210103_P01_WALL-PANEL-ASSY-SIDE-UPPER-LH_CAD (Autodesk Fusion 360 design; units mm, degrees)
part number: 2026-11-01-01-54-37-587
description: WALL - PANEL FRAME - SIDE UPPER - LH | Vách trái - khung trên | P01
part number: 211103
description: WALL - SKIN - SIDE UPPER - LH | Vách trái - tấm ốp alu trên | P01
part number: 211303
description: WALL - CAVITY FILL - SIDE UPPER - LH | Vách trái - bông PET trên | P01
part number: 211503
description: HARDWARE - STOP WASHER - Ø10.5 X Ø20 X 1.5 - AL | Long đen chặn nhôm | P01
part number: 831002
description: HARDWARE - RIVET NUT - M6 - SHEREX CAH3-610-4.2 | Tán rút M6 | P01
part number: 838003
Autodesk Fusion 360 part; units mm, degrees
(part 1 of 2)
ref_plane "WorkPlane1" through (0, 0, 1257.26) normal (0, 0, 1) x (1, 0, 0) in component "211103 WALL - PANEL FRAME - SIDE UPPER - LH"
sketch "SKETCH - RAIL - BOTTOM TUBE" plane through (0, 0, 1257.26) normal (0, 0, 1) x (1, 0, 0) in component "211103 WALL - PANEL FRAME - SIDE UPPER - LH"
  line L0 (-1244, -642.74) -> (-1204, -642.74)
  line L1 (-1204, -642.74) -> (-1204, 847)
  line L2 (-1204, 847) -> (-1244, 847)
  line L3 (-1244, 847) -> (-1244, -642.74)
  dimension "d662" = 40
  dimension "d663" = 1489.74
  dimension "d664" = 1244
  dimension "d665" = 642.74
  constraint horizontal L0
  constraint vertical L1
  constraint horizontal L2
  constraint vertical L3
  measures "d662" horizontal distance of L0.start L0.end
  measures "d663" vertical distance of L0.start L2.end
  measures "d664" horizontal distance of origin L0.start
  measures "d665" vertical distance of origin L0.start
extrude "EXTRUDE - RAIL - BOTTOM TUBE" add sketch "SKETCH - RAIL - BOTTOM TUBE" along normal blind 20 makes body 1 in component "211103 WALL - PANEL FRAME - SIDE UPPER - LH"
ref_plane "WorkPlane2" through (0, 0, 1258.46) normal (0, 0, 1) x (1, 0, 0) in component "211103 WALL - PANEL FRAME - SIDE UPPER - LH"
sketch "SKETCH - RAIL - BOTTOM BORE" plane through (0, 0, 1258.46) normal (0, 0, 1) x (1, 0, 0) in component "211103 WALL - PANEL FRAME - SIDE UPPER - LH"
  line L0 (-1242.8, -642.74) -> (-1205.2, -642.74)
  line L1 (-1205.2, -642.74) -> (-1205.2, 847)
  line L2 (-1205.2, 847) -> (-1242.8, 847)
  line L3 (-1242.8, 847) -> (-1242.8, -642.74)
  dimension "d670" = 37.6
  dimension "d671" = 1489.74
  dimension "d672" = 1242.8
  dimension "d673" = 642.74
  constraint horizontal L0
  constraint vertical L1
  constraint horizontal L2
  constraint vertical L3
  measures "d670" horizontal distance of L0.start L0.end
  measures "d671" vertical distance of L0.start L2.end
  measures "d672" horizontal distance of origin L0.start
  measures "d673" vertical distance of origin L0.start
extrude "CUT - RAIL - BOTTOM BORE" cut sketch "SKETCH - RAIL - BOTTOM BORE" along normal blind 17.6 bodies 1 in component "211103 WALL - PANEL FRAME - SIDE UPPER - LH"
ref_plane "WorkPlane3" through (0, 0, 2360) normal (0, 0, 1) x (1, 0, 0) in component "211103 WALL - PANEL FRAME - SIDE UPPER - LH"
sketch "SKETCH - RAIL - TOP TUBE" plane through (0, 0, 2360) normal (0, 0, 1) x (1, 0, 0) in component "211103 WALL - PANEL FRAME - SIDE UPPER - LH"
  line L0 (-1244, -642.74) -> (-1204, -642.74)
  line L1 (-1204, -642.74) -> (-1204, 847)
  line L2 (-1204, 847) -> (-1244, 847)
  line L3 (-1244, 847) -> (-1244, -642.74)
  dimension "d678" = 40
  dimension "d679" = 1489.74
  dimension "d680" = 1244
  dimension "d681" = 642.74
  constraint horizontal L0
  constraint vertical L1
  constraint horizontal L2
  constraint vertical L3
  measures "d678" horizontal distance of L0.start L0.end
  measures "d679" vertical distance of L0.start L2.end
  measures "d680" horizontal distance of origin L0.start
  measures "d681" vertical distance of origin L0.start
extrude "EXTRUDE - RAIL - TOP TUBE" add sketch "SKETCH - RAIL - TOP TUBE" along normal blind 40 separate body makes body 2 in component "211103 WALL - PANEL FRAME - SIDE UPPER - LH"
ref_plane "WorkPlane4" through (0, 0, 2361.2) normal (0, 0, 1) x (1, 0, 0) in component "211103 WALL - PANEL FRAME - SIDE UPPER - LH"
sketch "SKETCH - RAIL - TOP BORE" plane through (0, 0, 2361.2) normal (0, 0, 1) x (1, 0, 0) in component "211103 WALL - PANEL FRAME - SIDE UPPER - LH"
  line L0 (-1242.8, -642.74) -> (-1205.2, -642.74)
  line L1 (-1205.2, -642.74) -> (-1205.2, 847)
  line L2 (-1205.2, 847) -> (-1242.8, 847)
  line L3 (-1242.8, 847) -> (-1242.8, -642.74)
  dimension "d686" = 37.6
  dimension "d687" = 1489.74
  dimension "d688" = 1242.8
  dimension "d689" = 642.74
  constraint horizontal L0
  constraint vertical L1
  constraint horizontal L2
  constraint vertical L3
  measures "d686" horizontal distance of L0.start L0.end
  measures "d687" vertical distance of L0.start L2.end
  measures "d688" horizontal distance of origin L0.start
  measures "d689" vertical distance of origin L0.start
extrude "CUT - RAIL - TOP BORE" cut sketch "SKETCH - RAIL - TOP BORE" along normal blind 37.6 bodies 2 in component "211103 WALL - PANEL FRAME - SIDE UPPER - LH"
ref_plane "WorkPlane5" through (0, 0, 1277.26) normal (0, 0, 1) x (1, 0, 0) in component "211103 WALL - PANEL FRAME - SIDE UPPER - LH"
sketch "SKETCH - STILE - FRONT TUBE" plane through (0, 0, 1277.26) normal (0, 0, 1) x (1, 0, 0) in component "211103 WALL - PANEL FRAME - SIDE UPPER - LH"
  line L0 (-1244, -642.74) -> (-1204, -642.74)
  line L1 (-1204, -642.74) -> (-1204, -622.74)
  line L2 (-1204, -622.74) -> (-1244, -622.74)
  line L3 (-1244, -622.74) -> (-1244, -642.74)
  dimension "d694" = 40
  dimension "d695" = 20
  dimension "d696" = 1244
  dimension "d697" = 642.74
  constraint horizontal L0
  constraint vertical L1
  constraint horizontal L2
  constraint vertical L3
  measures "d694" horizontal distance of L0.start L0.end
  measures "d695" vertical distance of L0.start L2.end
  measures "d696" horizontal distance of origin L0.start
  measures "d697" vertical distance of origin L0.start
extrude "EXTRUDE - STILE - FRONT TUBE" add sketch "SKETCH - STILE - FRONT TUBE" along normal blind 1082.74 separate body makes body 3 in component "211103 WALL - PANEL FRAME - SIDE UPPER - LH"
ref_plane "WorkPlane6" through (0, 0, 1277.26) normal (0, 0, 1) x (1, 0, 0) in component "211103 WALL - PANEL FRAME - SIDE UPPER - LH"
sketch "SKETCH - STILE - FRONT BORE" plane through (0, 0, 1277.26) normal (0, 0, 1) x (1, 0, 0) in component "211103 WALL - PANEL FRAME - SIDE UPPER - LH"
  line L0 (-1242.8, -641.54) -> (-1205.2, -641.54)
  line L1 (-1205.2, -641.54) -> (-1205.2, -623.94)
  line L2 (-1205.2, -623.94) -> (-1242.8, -623.94)
  line L3 (-1242.8, -623.94) -> (-1242.8, -641.54)
  dimension "d702" = 37.6
  dimension "d703" = 17.6
  dimension "d704" = 1242.8
  dimension "d705" = 641.54
  constraint horizontal L0
  constraint vertical L1
  constraint horizontal L2
  constraint vertical L3
  measures "d702" horizontal distance of L0.start L0.end
  measures "d703" vertical distance of L0.start L2.end
  measures "d704" horizontal distance of origin L0.start
  measures "d705" vertical distance of origin L0.start
extrude "CUT - STILE - FRONT BORE" cut sketch "SKETCH - STILE - FRONT BORE" along normal blind 1082.74 bodies 3 in component "211103 WALL - PANEL FRAME - SIDE UPPER - LH"
ref_plane "WorkPlane7" through (0, 0, 1277.26) normal (0, 0, 1) x (1, 0, 0) in component "211103 WALL - PANEL FRAME - SIDE UPPER - LH"
sketch "SKETCH - STILE - BACK TUBE" plane through (0, 0, 1277.26) normal (0, 0, 1) x (1, 0, 0) in component "211103 WALL - PANEL FRAME - SIDE UPPER - LH"
  line L0 (-1244, 807) -> (-1204, 807)
  line L1 (-1204, 807) -> (-1204, 847)
  line L2 (-1204, 847) -> (-1244, 847)
  line L3 (-1244, 847) -> (-1244, 807)
  dimension "d710" = 40
  dimension "d711" = 40
  dimension "d712" = 1244
  dimension "d713" = 807
  constraint horizontal L0
  constraint vertical L1
  constraint horizontal L2
  constraint vertical L3
  measures "d710" horizontal distance of L0.start L0.end
  measures "d711" vertical distance of L0.start L2.end
  measures "d712" horizontal distance of origin L0.start
  measures "d713" vertical distance of origin L0.start
extrude "EXTRUDE - STILE - BACK TUBE" add sketch "SKETCH - STILE - BACK TUBE" along normal blind 1082.74 separate body makes body 4 in component "211103 WALL - PANEL FRAME - SIDE UPPER - LH"
ref_plane "WorkPlane8" through (0, 0, 1277.26) normal (0, 0, 1) x (1, 0, 0) in component "211103 WALL - PANEL FRAME - SIDE UPPER - LH"
sketch "SKETCH - STILE - BACK BORE" plane through (0, 0, 1277.26) normal (0, 0, 1) x (1, 0, 0) in component "211103 WALL - PANEL FRAME - SIDE UPPER - LH"
  line L0 (-1242.8, 808.2) -> (-1205.2, 808.2)
  line L1 (-1205.2, 808.2) -> (-1205.2, 845.8)
  line L2 (-1205.2, 845.8) -> (-1242.8, 845.8)
  line L3 (-1242.8, 845.8) -> (-1242.8, 808.2)
  dimension "d718" = 37.6
  dimension "d719" = 37.6
  dimension "d720" = 1242.8
  dimension "d721" = 808.2
  constraint horizontal L0
  constraint vertical L1
  constraint horizontal L2
  constraint vertical L3
  measures "d718" horizontal distance of L0.start L0.end
  measures "d719" vertical distance of L0.start L2.end
  measures "d720" horizontal distance of origin L0.start
  measures "d721" vertical distance of origin L0.start
extrude "CUT - STILE - BACK BORE" cut sketch "SKETCH - STILE - BACK BORE" along normal blind 1082.74 bodies 4 in component "211103 WALL - PANEL FRAME - SIDE UPPER - LH"
ref_plane "WorkPlane9" through (0, 0, 1277.26) normal (0, 0, 1) x (1, 0, 0) in component "211103 WALL - PANEL FRAME - SIDE UPPER - LH"
sketch "SKETCH - STILE - MID 1 TUBE" plane through (0, 0, 1277.26) normal (0, 0, 1) x (1, 0, 0) in component "211103 WALL - PANEL FRAME - SIDE UPPER - LH"
  line L0 (-1244, -277.805) -> (-1204, -277.805)
  line L1 (-1204, -277.805) -> (-1204, -257.805)
  line L2 (-1204, -257.805) -> (-1244, -257.805)
  line L3 (-1244, -257.805) -> (-1244, -277.805)
  dimension "d726" = 40
  dimension "d727" = 20
  dimension "d728" = 1244
  dimension "d729" = 277.805
  constraint horizontal L0
  constraint vertical L1
  constraint horizontal L2
  constraint vertical L3
  measures "d726" horizontal distance of L0.start L0.end
  measures "d727" vertical distance of L0.start L2.end
  measures "d728" horizontal distance of origin L0.start
  measures "d729" vertical distance of origin L0.start
extrude "EXTRUDE - STILE - MID 1 TUBE" add sketch "SKETCH - STILE - MID 1 TUBE" along normal blind 1082.74 separate body makes body 5 in component "211103 WALL - PANEL FRAME - SIDE UPPER - LH"
ref_plane "WorkPlane10" through (0, 0, 1277.26) normal (0, 0, 1) x (1, 0, 0) in component "211103 WALL - PANEL FRAME - SIDE UPPER - LH"
sketch "SKETCH - STILE - MID 1 BORE" plane through (0, 0, 1277.26) normal (0, 0, 1) x (1, 0, 0) in component "211103 WALL - PANEL FRAME - SIDE UPPER - LH"
  line L0 (-1243, -276.805) -> (-1205, -276.805)
  line L1 (-1205, -276.805) -> (-1205, -258.805)
  line L2 (-1205, -258.805) -> (-1243, -258.805)
  line L3 (-1243, -258.805) -> (-1243, -276.805)
  dimension "d734" = 38
  dimension "d735" = 18
  dimension "d736" = 1243
  dimension "d737" = 276.805
  constraint horizontal L0
  constraint vertical L1
  constraint horizontal L2
  constraint vertical L3
  measures "d734" horizontal distance of L0.start L0.end
  measures "d735" vertical distance of L0.start L2.end
  measures "d736" horizontal distance of origin L0.start
  measures "d737" vertical distance of origin L0.start
extrude "CUT - STILE - MID 1 BORE" cut sketch "SKETCH - STILE - MID 1 BORE" along normal blind 1082.74 bodies 5 in component "211103 WALL - PANEL FRAME - SIDE UPPER - LH"
pattern_linear "PATTERN - STILES - MID" count 3 spacing 364.935 along (0, 1, 0) of bodies 5 makes body 6 at (-1217.3333, 107.13, 1999.0867) makes body 7 at (-1217.3333, 472.065, 1999.0867) in component "211103 WALL - PANEL FRAME - SIDE UPPER - LH"
ref_plane "WorkPlane1" through (0, 0, 1257.26) normal (0, 0, 1) x (1, 0, 0) in component "211303 WALL - SKIN - SIDE UPPER - LH"
sketch "SKETCH - SKIN PLATE" plane through (0, 0, 1257.26) normal (0, 0, 1) x (1, 0, 0) in component "211303 WALL - SKIN - SIDE UPPER - LH"
  line L0 (-1250, -642.74) -> (-1247, -642.74)
  line L1 (-1247, -642.74) -> (-1247, 850)
  line L2 (-1247, 850) -> (-1250, 850)
  line L3 (-1250, 850) -> (-1250, -642.74)
  dimension "d746" = 3
  dimension "d747" = 1492.74
  dimension "d748" = 1250
  dimension "d749" = 642.74
  constraint horizontal L0
  constraint vertical L1
  constraint horizontal L2
  constraint vertical L3
  measures "d746" horizontal distance of L0.start L0.end
  measures "d747" vertical distance of L0.start L2.end
  measures "d748" horizontal distance of origin L0.start
  measures "d749" vertical distance of origin L0.start
extrude "EXTRUDE - SKIN PLATE" add sketch "SKETCH - SKIN PLATE" along normal blind 1142.74 separate body makes body 8 in component "211303 WALL - SKIN - SIDE UPPER - LH"
ref_plane "WorkPlane2" through (0, 0, 1257.26) normal (0, 0, 1) x (1, 0, 0) in component "211303 WALL - SKIN - SIDE UPPER - LH"
sketch "SKETCH - SKIN BACK RETURN" plane through (0, 0, 1257.26) normal (0, 0, 1) x (1, 0, 0) in component "211303 WALL - SKIN - SIDE UPPER - LH"
  line L0 (-1247, 847) -> (-1204, 847)
  line L1 (-1204, 847) -> (-1204, 850)
  line L2 (-1204, 850) -> (-1247, 850)
  line L3 (-1247, 850) -> (-1247, 847)
  dimension "d754" = 43
  dimension "d755" = 3
  dimension "d756" = 1247
  dimension "d757" = 847
  constraint horizontal L0
  constraint vertical L1
  constraint horizontal L2
  constraint vertical L3
  measures "d754" horizontal distance of L0.start L0.end
  measures "d755" vertical distance of L0.start L2.end
  measures "d756" horizontal distance of origin L0.start
  measures "d757" vertical distance of origin L0.start
extrude "JOIN - SKIN BACK RETURN" add sketch "SKETCH - SKIN BACK RETURN" along normal blind 1142.74 bodies 8 in component "211303 WALL - SKIN - SIDE UPPER - LH"
ref_plane "WorkPlane1" through (0, 0, 1277.26) normal (0, 0, 1) x (1, 0, 0) in component "211503 WALL - CAVITY FILL - SIDE UPPER - LH"
sketch "SKETCH - FILL BAY 1" plane through (0, 0, 1277.26) normal (0, 0, 1) x (1, 0, 0) in component "211503 WALL - CAVITY FILL - SIDE UPPER - LH"
  line L0 (-1244, -622.74) -> (-1204, -622.74)
  line L1 (-1204, -622.74) -> (-1204, -277.805)
  line L2 (-1204, -277.805) -> (-1244, -277.805)
  line L3 (-1244, -277.805) -> (-1244, -622.74)
  dimension "d762" = 40
  dimension "d763" = 344.935
  dimension "d764" = 1244
  dimension "d765" = 622.74
  constraint horizontal L0
  constraint vertical L1
  constraint horizontal L2
  constraint vertical L3
  measures "d762" horizontal distance of L0.start L0.end
  measures "d763" vertical distance of L0.start L2.end
  measures "d764" horizontal distance of origin L0.start
  measures "d765" vertical distance of origin L0.start
extrude "EXTRUDE - FILL BAY 1" add sketch "SKETCH - FILL BAY 1" along normal blind 1082.74 separate body makes body 9 in component "211503 WALL - CAVITY FILL - SIDE UPPER - LH"
pattern_linear "PATTERN - FILL BAYS" count 3 spacing 364.935 along (0, 1, 0) of bodies 9 makes body 10 at (-1244, -27.8483, 1999.0867) makes body 11 at (-1244, 337.0867, 1999.0867) in component "211503 WALL - CAVITY FILL - SIDE UPPER - LH"
ref_plane "WorkPlane2" through (0, 0, 1277.26) normal (0, 0, 1) x (1, 0, 0) in component "211503 WALL - CAVITY FILL - SIDE UPPER - LH"
sketch "SKETCH - FILL BAY LAST" plane through (0, 0, 1277.26) normal (0, 0, 1) x (1, 0, 0) in component "211503 WALL - CAVITY FILL - SIDE UPPER - LH"
  line L0 (-1244, 472.065) -> (-1204, 472.065)
  line L1 (-1204, 472.065) -> (-1204, 807)
  line L2 (-1204, 807) -> (-1244, 807)
  line L3 (-1244, 807) -> (-1244, 472.065)
  dimension "d774" = 40
  dimension "d775" = 334.935
  dimension "d776" = 1244
  dimension "d777" = 472.065
  constraint horizontal L0
  constraint vertical L1
  constraint horizontal L2
  constraint vertical L3
  measures "d774" horizontal distance of L0.start L0.end
  measures "d775" vertical distance of L0.start L2.end
  measures "d776" horizontal distance of origin L0.start
  measures "d777" vertical distance of origin L0.start
extrude "EXTRUDE - FILL BAY LAST" add sketch "SKETCH - FILL BAY LAST" along normal blind 1082.74 separate body makes body 12 in component "211503 WALL - CAVITY FILL - SIDE UPPER - LH"
ref_plane "WorkPlane3" through (0, 0, 1277.26) normal (0, 0, 1) x (1, 0, 0) in component "211503 WALL - CAVITY FILL - SIDE UPPER - LH"
sketch "SKETCH - FILL POCKET BOTTOM BOLT 1" plane through (0, 0, 1277.26) normal (0, 0, 1) x (1, 0, 0) in component "211503 WALL - CAVITY FILL - SIDE UPPER - LH"
  line L0 (-1244, -452.74) -> (-1204, -452.74)
  line L1 (-1204, -452.74) -> (-1204, -392.74)
  line L2 (-1204, -392.74) -> (-1244, -392.74)
  line L3 (-1244, -392.74) -> (-1244, -452.74)
  dimension "d782" = 40
  dimension "d783" = 60
  dimension "d784" = 1244
  dimension "d785" = 452.74
  constraint horizontal L0
  constraint vertical L1
  constraint horizontal L2
  constraint vertical L3
  measures "d782" horizontal distance of L0.start L0.end
  measures "d783" vertical distance of L0.start L2.end
  measures "d784" horizontal distance of origin L0.start
  measures "d785" vertical distance of origin L0.start
extrude "CUT - FILL POCKET BOTTOM BOLT 1" cut sketch "SKETCH - FILL POCKET BOTTOM BOLT 1" along normal blind 60 bodies 9 in component "211503 WALL - CAVITY FILL - SIDE UPPER - LH"
ref_plane "WorkPlane4" through (0, 0, 1277.26) normal (0, 0, 1) x (1, 0, 0) in component "211503 WALL - CAVITY FILL - SIDE UPPER - LH"
sketch "SKETCH - FILL POCKET BOTTOM BOLT 2" plane through (0, 0, 1277.26) normal (0, 0, 1) x (1, 0, 0) in component "211503 WALL - CAVITY FILL - SIDE UPPER - LH"
  line L0 (-1244, -101.8267) -> (-1204, -101.8267)
  line L1 (-1204, -101.8267) -> (-1204, -41.8267)
  line L2 (-1204, -41.8267) -> (-1244, -41.8267)
  line L3 (-1244, -41.8267) -> (-1244, -101.8267)
  dimension "d790" = 40
  dimension "d791" = 60
  dimension "d792" = 1244
  dimension "d793" = 101.8267
  constraint horizontal L0
  constraint vertical L1
  constraint horizontal L2
  constraint vertical L3
  measures "d790" horizontal distance of L0.start L0.end
  measures "d791" vertical distance of L0.start L2.end
  measures "d792" horizontal distance of origin L0.start
  measures "d793" vertical distance of origin L0.start
extrude "CUT - FILL POCKET BOTTOM BOLT 2" cut sketch "SKETCH - FILL POCKET BOTTOM BOLT 2" along normal blind 60 bodies 10 in component "211503 WALL - CAVITY FILL - SIDE UPPER - LH"
ref_plane "WorkPlane5" through (0, 0, 1277.26) normal (0, 0, 1) x (1, 0, 0) in component "211503 WALL - CAVITY FILL - SIDE UPPER - LH"
sketch "SKETCH - FILL POCKET BOTTOM BOLT 3" plane through (0, 0, 1277.26) normal (0, 0, 1) x (1, 0, 0) in component "211503 WALL - CAVITY FILL - SIDE UPPER - LH"
  line L0 (-1244, 249.0867) -> (-1204, 249.0867)
  line L1 (-1204, 249.0867) -> (-1204, 309.0867)
  line L2 (-1204, 309.0867) -> (-1244, 309.0867)
  line L3 (-1244, 309.0867) -> (-1244, 249.0867)
  dimension "d798" = 40
  dimension "d799" = 60
  dimension "d800" = 1244
  dimension "d801" = 249.0867
  constraint horizontal L0
  constraint vertical L1
  constraint horizontal L2
  constraint vertical L3
  measures "d798" horizontal distance of L0.start L0.end
  measures "d799" vertical distance of L0.start L2.end
  measures "d800" horizontal distance of origin L0.start
  measures "d801" vertical distance of origin L0.start
extrude "CUT - FILL POCKET BOTTOM BOLT 3" cut sketch "SKETCH - FILL POCKET BOTTOM BOLT 3" along normal blind 60 bodies 11 in component "211503 WALL - CAVITY FILL - SIDE UPPER - LH"
ref_plane "WorkPlane6" through (0, 0, 1277.26) normal (0, 0, 1) x (1, 0, 0) in component "211503 WALL - CAVITY FILL - SIDE UPPER - LH"
sketch "SKETCH - FILL POCKET BOTTOM BOLT 4" plane through (0, 0, 1277.26) normal (0, 0, 1) x (1, 0, 0) in component "211503 WALL - CAVITY FILL - SIDE UPPER - LH"
  line L0 (-1244, 600) -> (-1204, 600)
  line L1 (-1204, 600) -> (-1204, 660)
  line L2 (-1204, 660) -> (-1244, 660)
  line L3 (-1244, 660) -> (-1244, 600)
  dimension "d806" = 40
  dimension "d807" = 60
  dimension "d808" = 1244
  dimension "d809" = 600
  constraint horizontal L0
  constraint vertical L1
  constraint horizontal L2
  constraint vertical L3
  measures "d806" horizontal distance of L0.start L0.end
  measures "d807" vertical distance of L0.start L2.end
  measures "d808" horizontal distance of origin L0.start
  measures "d809" vertical distance of origin L0.start
extrude "CUT - FILL POCKET BOTTOM BOLT 4" cut sketch "SKETCH - FILL POCKET BOTTOM BOLT 4" along normal blind 60 bodies 12 in component "211503 WALL - CAVITY FILL - SIDE UPPER - LH"
ref_plane "WorkPlane7" through (0, 0, 1447.26) normal (0, 0, 1) x (1, 0, 0) in component "211503 WALL - CAVITY FILL - SIDE UPPER - LH"
sketch "SKETCH - FILL POCKET DECOR BOLT 1" plane through (0, 0, 1447.26) normal (0, 0, 1) x (1, 0, 0) in component "211503 WALL - CAVITY FILL - SIDE UPPER - LH"
  line L0 (-1244, -622.74) -> (-1204, -622.74)
  line L1 (-1204, -622.74) -> (-1204, -562.74)
  line L2 (-1204, -562.74) -> (-1244, -562.74)
  line L3 (-1244, -562.74) -> (-1244, -622.74)
  dimension "d814" = 40
  dimension "d815" = 60
  dimension "d816" = 1244
  dimension "d817" = 622.74
  constraint horizontal L0
  constraint vertical L1
  constraint horizontal L2
  constraint vertical L3
  measures "d814" horizontal distance of L0.start L0.end
  measures "d815" vertical distance of L0.start L2.end
  measures "d816" horizontal distance of origin L0.start
  measures "d817" vertical distance of origin L0.start
extrude "CUT - FILL POCKET DECOR BOLT 1" cut sketch "SKETCH - FILL POCKET DECOR BOLT 1" along normal blind 60 bodies 9 in component "211503 WALL - CAVITY FILL - SIDE UPPER - LH"
ref_plane "WorkPlane8" through (0, 0, 1798.63) normal (0, 0, 1) x (1, 0, 0) in component "211503 WALL - CAVITY FILL - SIDE UPPER - LH"
sketch "SKETCH - FILL POCKET DECOR BOLT 2" plane through (0, 0, 1798.63) normal (0, 0, 1) x (1, 0, 0) in component "211503 WALL - CAVITY FILL - SIDE UPPER - LH"
  line L0 (-1244, -622.74) -> (-1204, -622.74)
  line L1 (-1204, -622.74) -> (-1204, -562.74)
  line L2 (-1204, -562.74) -> (-1244, -562.74)
  line L3 (-1244, -562.74) -> (-1244, -622.74)
  dimension "d822" = 40
  dimension "d823" = 60
  dimension "d824" = 1244
  dimension "d825" = 622.74
  constraint horizontal L0
  constraint vertical L1
  constraint horizontal L2
  constraint vertical L3
  measures "d822" horizontal distance of L0.start L0.end
  measures "d823" vertical distance of L0.start L2.end
  measures "d824" horizontal distance of origin L0.start
  measures "d825" vertical distance of origin L0.start
extrude "CUT - FILL POCKET DECOR BOLT 2" cut sketch "SKETCH - FILL POCKET DECOR BOLT 2" along normal blind 60 bodies 9 in component "211503 WALL - CAVITY FILL - SIDE UPPER - LH"
ref_plane "WorkPlane9" through (0, 0, 2150) normal (0, 0, 1) x (1, 0, 0) in component "211503 WALL - CAVITY FILL - SIDE UPPER - LH"
sketch "SKETCH - FILL POCKET DECOR BOLT 3" plane through (0, 0, 2150) normal (0, 0, 1) x (1, 0, 0) in component "211503 WALL - CAVITY FILL - SIDE UPPER - LH"
  line L0 (-1244, -622.74) -> (-1204, -622.74)
  line L1 (-1204, -622.74) -> (-1204, -562.74)
  line L2 (-1204, -562.74) -> (-1244, -562.74)
  line L3 (-1244, -562.74) -> (-1244, -622.74)
  dimension "d830" = 40
  dimension "d831" = 60
  dimension "d832" = 1244
  dimension "d833" = 622.74
  constraint horizontal L0
  constraint vertical L1
  constraint horizontal L2
  constraint vertical L3
  measures "d830" horizontal distance of L0.start L0.end
  measures "d831" vertical distance of L0.start L2.end
  measures "d832" horizontal distance of origin L0.start
  measures "d833" vertical distance of origin L0.start
extrude "CUT - FILL POCKET DECOR BOLT 3" cut sketch "SKETCH - FILL POCKET DECOR BOLT 3" along normal blind 60 bodies 9 in component "211503 WALL - CAVITY FILL - SIDE UPPER - LH"
ref_plane "WorkPlane11" through (0, 0, 1257.26) normal (0, 0, 1) x (1, 0, 0) in component "211103 WALL - PANEL FRAME - SIDE UPPER - LH"
sketch "HOLE CENTRE - BOTTOM RAIL BOLT CLEARANCE 1" plane through (0, 0, 1257.26) normal (0, 0, 1) x (1, 0, 0) in component "211103 WALL - PANEL FRAME - SIDE UPPER - LH"
  point P0 (-1224, -422.74)
  dimension "d838" = 1224
  dimension "d839" = 422.74
  measures "d838" horizontal distance of origin P0
  measures "d839" vertical distance of origin P0
hole "HOLE - BOTTOM RAIL BOLT CLEARANCE 1" at (-1224, -422.74, 1257.26) direction (0, 0, 1) diameter 7 depth 1.2 tip angle 118 bodies 1 in component "211103 WALL - PANEL FRAME - SIDE UPPER - LH"
ref_plane "WorkPlane12" through (0, 0, 1277.26) normal (0, 0, 1) x (1, 0, 0) in component "211103 WALL - PANEL FRAME - SIDE UPPER - LH"
sketch "HOLE CENTRE - BOTTOM RAIL KEY ACCESS 1" plane through (0, 0, 1277.26) normal (0, 0, 1) x (1, 0, 0) in component "211103 WALL - PANEL FRAME - SIDE UPPER - LH"
  point P0 (-1224, -422.74)
  dimension "d845" = 1224
  dimension "d846" = 422.74
  measures "d845" horizontal distance of origin P0
  measures "d846" vertical distance of origin P0
hole "HOLE - BOTTOM RAIL KEY ACCESS 1" at (-1224, -422.74, 1277.26) direction (0, 0, -1) diameter 19 depth 1.2 tip angle 118 bodies 1 in component "211103 WALL - PANEL FRAME - SIDE UPPER - LH"
pattern_linear "PATTERN - BOTTOM RAIL BOLT HOLES" count 4 spacing 350.9133 along (0, 1, 0) of "HOLE - BOTTOM RAIL BOLT CLEARANCE 1", "HOLE - BOTTOM RAIL KEY ACCESS 1" in component "211103 WALL - PANEL FRAME - SIDE UPPER - LH"
ref_plane "WorkPlane13" through (0, 0, 1257.26) normal (0, 0, 1) x (1, 0, 0) in component "211103 WALL - PANEL FRAME - SIDE UPPER - LH"
sketch "HOLE CENTRE - BOTTOM RAIL SPIGOT ROUND" plane through (0, 0, 1257.26) normal (0, 0, 1) x (1, 0, 0) in component "211103 WALL - PANEL FRAME - SIDE UPPER - LH"
  point P0 (-1224, -542.74)
  dimension "d856" = 1224
  dimension "d857" = 542.74
  measures "d856" horizontal distance of origin P0
  measures "d857" vertical distance of origin P0
hole "HOLE - BOTTOM RAIL SPIGOT ROUND" at (-1224, -542.74, 1257.26) direction (0, 0, 1) diameter 8.5 depth 1.2 tip angle 118 bodies 1 in component "211103 WALL - PANEL FRAME - SIDE UPPER - LH"
ref_plane "WorkPlane14" through (0, 0, 1257.26) normal (0, 0, 1) x (1, 0, 0) in component "211103 WALL - PANEL FRAME - SIDE UPPER - LH"
sketch "SKETCH - BOTTOM RAIL SPIGOT SLOT" plane through (0, 0, 1257.26) normal (0, 0, 1) x (1, 0, 0) in component "211103 WALL - PANEL FRAME - SIDE UPPER - LH"
  line L0 (-1226.75, 745.75) -> (-1221.25, 745.75)
  line L1 (-1221.25, 745.75) -> (-1221.25, 754.25)
  line L2 (-1221.25, 754.25) -> (-1226.75, 754.25)
  line L3 (-1226.75, 754.25) -> (-1226.75, 745.75)
  dimension "d863" = 5.5
  dimension "d864" = 8.5
  dimension "d865" = 1226.75
  dimension "d866" = 745.75
  constraint horizontal L0
  constraint vertical L1
  constraint horizontal L2
  constraint vertical L3
  measures "d863" horizontal distance of L0.start L0.end
  measures "d864" vertical distance of L0.start L2.end
  measures "d865" horizontal distance of origin L0.start
  measures "d866" vertical distance of origin L0.start
extrude "CUT - BOTTOM RAIL SPIGOT SLOT" cut sketch "SKETCH - BOTTOM RAIL SPIGOT SLOT" along normal blind 1.2 bodies 1 in component "211103 WALL - PANEL FRAME - SIDE UPPER - LH"
ref_plane "WorkPlane15" through (0, 0, 1257.26) normal (0, 0, 1) x (1, 0, 0) in component "211103 WALL - PANEL FRAME - SIDE UPPER - LH"
sketch "HOLE CENTRE - BOTTOM RAIL SPIGOT SLOT END 1" plane through (0, 0, 1257.26) normal (0, 0, 1) x (1, 0, 0) in component "211103 WALL - PANEL FRAME - SIDE UPPER - LH"
  point P0 (-1226.75, 750)
  dimension "d871" = 1226.75
  dimension "d872" = 750
  measures "d871" horizontal distance of origin P0
  measures "d872" vertical distance of origin P0
hole "HOLE - BOTTOM RAIL SPIGOT SLOT END 1" at (-1226.75, 750, 1257.26) direction (0, 0, 1) diameter 8.5 depth 1.2 tip angle 118 bodies 1 in component "211103 WALL - PANEL FRAME - SIDE UPPER - LH"
ref_plane "WorkPlane16" through (0, 0, 1257.26) normal (0, 0, 1) x (1, 0, 0) in component "211103 WALL - PANEL FRAME - SIDE UPPER - LH"
sketch "HOLE CENTRE - BOTTOM RAIL SPIGOT SLOT END 2" plane through (0, 0, 1257.26) normal (0, 0, 1) x (1, 0, 0) in component "211103 WALL - PANEL FRAME - SIDE UPPER - LH"
  point P0 (-1221.25, 750)
  dimension "d878" = 1221.25
  dimension "d879" = 750
  measures "d878" horizontal distance of origin P0
  measures "d879" vertical distance of origin P0
hole "HOLE - BOTTOM RAIL SPIGOT SLOT END 2" at (-1221.25, 750, 1257.26) direction (0, 0, 1) diameter 8.5 depth 1.2 tip angle 118 bodies 1 in component "211103 WALL - PANEL FRAME - SIDE UPPER - LH"
ref_plane "WorkPlane17" through (-1204, 0, 0) normal (1, 0, 0) x (0, 1, 0) in component "211103 WALL - PANEL FRAME - SIDE UPPER - LH"
sketch "HOLE CENTRE - TOP MEMBER CEILING RIVNUT 1" plane through (-1204, 0, 0) normal (1, 0, 0) x (0, 0, -1) in component "211103 WALL - PANEL FRAME - SIDE UPPER - LH"
  point P0 (-2374, -425)
  dimension "d885" = 425
  dimension "d886" = 2374
  measures "d885" vertical distance of origin P0
  measures "d886" horizontal distance of origin P0
hole "HOLE - TOP MEMBER CEILING RIVNUT 1" at (-1204, -425, 2374) direction (-1, 0, 0) diameter 9.53 depth 1.2 tip angle 118 bodies 2 in component "211103 WALL - PANEL FRAME - SIDE UPPER - LH"
pattern_linear "PATTERN - TOP MEMBER CEILING RIVNUTS" count 4 spacing 351.6667 along (0, 1, 0) of "HOLE - TOP MEMBER CEILING RIVNUT 1" in component "211103 WALL - PANEL FRAME - SIDE UPPER - LH"
ref_plane "WorkPlane18" through (0, -642.74, 0) normal (0, 1, 0) x (0, 0, 1) in component "211103 WALL - PANEL FRAME - SIDE UPPER - LH"
sketch "HOLE CENTRE - FRONT STILE BOLT CLEARANCE 1" plane through (0, -642.74, 0) normal (0, 1, 0) x (1, 0, 0) in component "211103 WALL - PANEL FRAME - SIDE UPPER - LH"
  point P0 (-1224, -1477.26)
  dimension "d896" = 1224
  dimension "d897" = 1477.26
  measures "d896" horizontal distance of origin P0
  measures "d897" vertical distance of origin P0
hole "HOLE - FRONT STILE BOLT CLEARANCE 1" at (-1224, -642.74, 1477.26) direction (0, 1, 0) diameter 7 depth 1.2 tip angle 118 bodies 3 in component "211103 WALL - PANEL FRAME - SIDE UPPER - LH"
ref_plane "WorkPlane19" through (0, -622.74, 0) normal (0, 1, 0) x (0, 0, 1) in component "211103 WALL - PANEL FRAME - SIDE UPPER - LH"
sketch "HOLE CENTRE - FRONT STILE KEY ACCESS 1" plane through (0, -622.74, 0) normal (0, 1, 0) x (1, 0, 0) in component "211103 WALL - PANEL FRAME - SIDE UPPER - LH"
  point P0 (-1224, -1477.26)
  dimension "d903" = 1224
  dimension "d904" = 1477.26
  measures "d903" horizontal distance of origin P0
  measures "d904" vertical distance of origin P0
hole "HOLE - FRONT STILE KEY ACCESS 1" at (-1224, -622.74, 1477.26) direction (0, -1, 0) diameter 19 depth 1.2 tip angle 118 bodies 3 in component "211103 WALL - PANEL FRAME - SIDE UPPER - LH"
pattern_linear "PATTERN - FRONT STILE BOLT HOLES" count 3 spacing 351.37 along (0, 0, 1) of "HOLE - FRONT STILE BOLT CLEARANCE 1", "HOLE - FRONT STILE KEY ACCESS 1" in component "211103 WALL - PANEL FRAME - SIDE UPPER - LH"
ref_plane "WorkPlane20" through (-1204, 0, 0) normal (1, 0, 0) x (0, 1, 0) in component "211103 WALL - PANEL FRAME - SIDE UPPER - LH"
sketch "HOLE CENTRE - BACK STILE CORNER RIVNUT 1" plane through (-1204, 0, 0) normal (1, 0, 0) x (0, 0, -1) in component "211103 WALL - PANEL FRAME - SIDE UPPER - LH"
  point P0 (-1453.13, 824)
  dimension "d914" = 824
  dimension "d915" = 1453.13
  measures "d914" vertical distance of origin P0
  measures "d915" horizontal distance of origin P0
hole "HOLE - BACK STILE CORNER RIVNUT 1" at (-1204, 824, 1453.13) direction (-1, 0, 0) diameter 9.53 depth 1.2 tip angle 118 bodies 4 in component "211103 WALL - PANEL FRAME - SIDE UPPER - LH"
pattern_linear "PATTERN - BACK STILE CORNER RIVNUTS" count 3 spacing 339.305 along (0, 0, 1) of "HOLE - BACK STILE CORNER RIVNUT 1" in component "211103 WALL - PANEL FRAME - SIDE UPPER - LH"
ref_plane "WorkPlane1" through (-1204, 0, 0) normal (1, 0, 0) x (0, 1, 0) in component "831002 HARDWARE - STOP WASHER - Ø10.5 X Ø20 X 1.5 - AL"
sketch "SKETCH - STOP WASHER TOP MEMBER CEILING" plane through (-1204, 0, 0) normal (1, 0, 0) x (0, 0, -1) in component "831002 HARDWARE - STOP WASHER - Ø10.5 X Ø20 X 1.5 - AL"
  circle A0 centre (-2374, -425) radius 10
  circle A1 centre (-2374, -425) radius 5.25
  dimension "d925" = 425
  dimension "d926" = 2374
  dimension "d927" = 20
  dimension "d928" = 10.5
  measures "d925" vertical distance of origin A0.centre
  measures "d926" horizontal distance of origin A0.centre
  measures "d927" diameter of A0
  measures "d928" diameter of A1
extrude "EXTRUDE - STOP WASHER TOP MEMBER CEILING" add sketch "SKETCH - STOP WASHER TOP MEMBER CEILING" along normal blind 1.5 separate body makes body 13 in component "831002 HARDWARE - STOP WASHER - Ø10.5 X Ø20 X 1.5 - AL"
ref_plane "WorkPlane1" through (-1202.5, 0, 0) normal (1, 0, 0) x (0, 1, 0) in component "838003 HARDWARE - RIVET NUT - M6 - SHEREX CAH3-610-4.2"
sketch "SKETCH - RIVNUT HEAD TOP MEMBER CEILING" plane through (-1202.5, 0, 0) normal (1, 0, 0) x (0, 0, -1) in component "838003 HARDWARE - RIVET NUT - M6 - SHEREX CAH3-610-4.2"
  circle A0 centre (-2374, -425) radius 6.48
  circle A1 centre (-2374, -425) radius 3
  dimension "d933" = 425
  dimension "d934" = 2374
  dimension "d935" = 12.96
  dimension "d936" = 6
  measures "d933" vertical distance of origin A0.centre
  measures "d934" horizontal distance of origin A0.centre
  measures "d935" diameter of A0
  measures "d936" diameter of A1
extrude "EXTRUDE - RIVNUT HEAD TOP MEMBER CEILING" add sketch "SKETCH - RIVNUT HEAD TOP MEMBER CEILING" along normal blind 0.76 separate body makes body 14 in component "838003 HARDWARE - RIVET NUT - M6 - SHEREX CAH3-610-4.2"
ref_plane "WorkPlane2" through (-1202.5, 0, 0) normal (1, 0, 0) x (0, 1, 0) in component "838003 HARDWARE - RIVET NUT - M6 - SHEREX CAH3-610-4.2"
sketch "SKETCH - RIVNUT BODY TOP MEMBER CEILING" plane through (-1202.5, 0, 0) normal (1, 0, 0) x (0, 0, -1) in component "838003 HARDWARE - RIVET NUT - M6 - SHEREX CAH3-610-4.2"
  circle A0 centre (-2374, -425) radius 4.75
  circle A1 centre (-2374, -425) radius 3
  dimension "d941" = 425
  dimension "d942" = 2374
  dimension "d943" = 9.5
  dimension "d944" = 6
  measures "d941" vertical distance of origin A0.centre
  measures "d942" horizontal distance of origin A0.centre
  measures "d943" diameter of A0
  measures "d944" diameter of A1
extrude "EXTRUDE - RIVNUT BODY TOP MEMBER CEILING" add sketch "SKETCH - RIVNUT BODY TOP MEMBER CEILING" against normal blind 10.16 separate body makes body 15 in component "838003 HARDWARE - RIVET NUT - M6 - SHEREX CAH3-610-4.2"
combine "COMBINE - RIVNUT TOP MEMBER CEILING" operation add target body 14 tool bodies 15 in component "838003 HARDWARE - RIVET NUT - M6 - SHEREX CAH3-610-4.2"
pattern_linear "PATTERN - STOP WASHER - TOP MEMBER CEILING" count 4 spacing 351.6667 along (0, 1, 0) of bodies 13 makes body 16 at (-1204, -68.2025, 2380.6436) makes body 17 at (-1204, 283.4641, 2367.3564) makes body 18 at (-1204, 624.8692, 2380.6436) in component "831002 HARDWARE - STOP WASHER - Ø10.5 X Ø20 X 1.5 - AL"
pattern_linear "PATTERN - RIVNUT - TOP MEMBER CEILING" count 4 spacing 351.6667 along (0, 1, 0) of bodies 14 makes body 19 at (-1209.2733, -69.3432, 2371.4229) makes body 20 at (-1209.2733, 282.3235, 2371.4229) makes body 21 at (-1209.2733, 631.8451, 2369.623) in component "838003 HARDWARE - RIVET NUT - M6 - SHEREX CAH3-610-4.2"
ref_plane "WorkPlane2" through (-1204, 0, 0) normal (1, 0, 0) x (0, 1, 0) in component "831002 HARDWARE - STOP WASHER - Ø10.5 X Ø20 X 1.5 - AL"
sketch "SKETCH - STOP WASHER BACK STILE CORNER" plane through (-1204, 0, 0) normal (1, 0, 0) x (0, 0, -1) in component "831002 HARDWARE - STOP WASHER - Ø10.5 X Ø20 X 1.5 - AL"
  circle A0 centre (-1453.13, 824) radius 10
  circle A1 centre (-1453.13, 824) radius 5.25
  dimension "d959" = 824
  dimension "d960" = 1453.13
  dimension "d961" = 20
  dimension "d962" = 10.5
  measures "d959" vertical distance of origin A0.centre
  measures "d960" horizontal distance of origin A0.centre
  measures "d961" diameter of A0
  measures "d962" diameter of A1
extrude "EXTRUDE - STOP WASHER BACK STILE CORNER" add sketch "SKETCH - STOP WASHER BACK STILE CORNER" along normal blind 1.5 separate body makes body 22 in component "831002 HARDWARE - STOP WASHER - Ø10.5 X Ø20 X 1.5 - AL"
ref_plane "WorkPlane3" through (-1202.5, 0, 0) normal (1, 0, 0) x (0, 1, 0) in component "838003 HARDWARE - RIVET NUT - M6 - SHEREX CAH3-610-4.2"
sketch "SKETCH - RIVNUT HEAD BACK STILE CORNER" plane through (-1202.5, 0, 0) normal (1, 0, 0) x (0, 0, -1) in component "838003 HARDWARE - RIVET NUT - M6 - SHEREX CAH3-610-4.2"
  circle A0 centre (-1453.13, 824) radius 6.48
  circle A1 centre (-1453.13, 824) radius 3
  dimension "d967" = 824
  dimension "d968" = 1453.13
  dimension "d969" = 12.96
  dimension "d970" = 6
  measures "d967" vertical distance of origin A0.centre
  measures "d968" horizontal distance of origin A0.centre
  measures "d969" diameter of A0
  measures "d970" diameter of A1
extrude "EXTRUDE - RIVNUT HEAD BACK STILE CORNER" add sketch "SKETCH - RIVNUT HEAD BACK STILE CORNER" along normal blind 0.76 separate body makes body 23 in component "838003 HARDWARE - RIVET NUT - M6 - SHEREX CAH3-610-4.2"
ref_plane "WorkPlane4" through (-1202.5, 0, 0) normal (1, 0, 0) x (0, 1, 0) in component "838003 HARDWARE - RIVET NUT - M6 - SHEREX CAH3-610-4.2"
sketch "SKETCH - RIVNUT BODY BACK STILE CORNER" plane through (-1202.5, 0, 0) normal (1, 0, 0) x (0, 0, -1) in component "838003 HARDWARE - RIVET NUT - M6 - SHEREX CAH3-610-4.2"
  circle A0 centre (-1453.13, 824) radius 4.75
  circle A1 centre (-1453.13, 824) radius 3
  dimension "d975" = 824
  dimension "d976" = 1453.13
  dimension "d977" = 9.5
  dimension "d978" = 6
  measures "d975" vertical distance of origin A0.centre
  measures "d976" horizontal distance of origin A0.centre
  measures "d977" diameter of A0
  measures "d978" diameter of A1
extrude "EXTRUDE - RIVNUT BODY BACK STILE CORNER" add sketch "SKETCH - RIVNUT BODY BACK STILE CORNER" against normal blind 10.16 separate body makes body 24 in component "838003 HARDWARE - RIVET NUT - M6 - SHEREX CAH3-610-4.2"
combine "COMBINE - RIVNUT BACK STILE CORNER" operation add target body 23 tool bodies 24 in component "838003 HARDWARE - RIVET NUT - M6 - SHEREX CAH3-610-4.2"
pattern_linear "PATTERN - STOP WASHER - BACK STILE CORNER" count 3 spacing 339.305 along (0, 0, 1) of bodies 22 makes body 25 at (-1204, 815.6811, 1793.5566) makes body 26 at (-1204, 829.3353, 2125.2595) in component "831002 HARDWARE - STOP WASHER - Ø10.5 X Ø20 X 1.5 - AL"
pattern_linear "PATTERN - RIVNUT - BACK STILE CORNER" count 3 spacing 339.305 along (0, 0, 1) of bodies 23 makes body 27 at (-1209.2733, 828.2269, 1790.268) makes body 28 at (-1209.2733, 825.8451, 2127.363) in component "838003 HARDWARE - RIVET NUT - M6 - SHEREX CAH3-610-4.2"
component "211103 WALL - PANEL FRAME - SIDE UPPER - LH" placed x (1, 0, 0) y (0, 1, 0) z (0, 0, 1) at (0, 0, 0)
component "211303 WALL - SKIN - SIDE UPPER - LH" placed x (1, 0, 0) y (0, 1, 0) z (0, 0, 1) at (0, 0, 0)
component "211503 WALL - CAVITY FILL - SIDE UPPER - LH" placed x (1, 0, 0) y (0, 1, 0) z (0, 0, 1) at (0, 0, 0)
component "831002 HARDWARE - STOP WASHER - Ø10.5 X Ø20 X 1.5 - AL" placed x (1, 0, 0) y (0, 1, 0) z (0, 0, 1) at (0, 0, 0)
component "838003 HARDWARE - RIVET NUT - M6 - SHEREX CAH3-610-4.2" placed x (1, 0, 0) y (0, 1, 0) z (0, 0, 1) at (0, 0, 0)
equation "pod_w_Ref = 2500 mm" comment "DECIDED: D-01; conventions s4 (X = +-1250)"
equation "pod_d_Ref = 1700 mm" comment "DECIDED: D-01; conventions s4 (Y = +-850)"
equation "pod_h_Ref = 2400 mm" comment "DECIDED: D-21 (room floor to roof skin top)"
equation "glide_h_Ref = 10 mm" comment "ASSUMPTION: layout study inputs.py glide_h"
equation "band_h_Ref = 100 mm" comment "SOURCE: layout study B1 list B-BAND 100x40; inputs.py base_h"
equation "outer_t_Ref = skin_t_Ref + bond_t_Ref + frame_t_Ref" comment "DECIDED: PM ruling 2026-10-31: ACP 3 + bond line 3 + frame 40, walls and ceiling (was 43)"
equation "cav_gap_Ref = 4 mm" comment "DECIDED: D-16, D-42: the gap between the outer panel and the lining cassette in the wall and ceiling stack"
equation "cass_t_Ref = 34 mm" comment "SOURCE: layout study B1 final list L-CASS 34 (tray + 25 gap + felt 9)"
equation "stack_t_Ref = outer_t_Ref + cav_gap_Ref + cass_t_Ref" comment "CALCULATION: D-16, D-42 stack, walls and ceiling: outer panel + cavity gap + cassette (PM ruling 2026-10-31 on outer_t)"
equation "wall_depth_Ref = 1495 mm" comment "DECIDED: PM ruling pass C: side walls start at the decor back plate (Y -645), as v1 (1496)"
equation "lin_gap_Ref = 4 mm" comment "ASSUMPTION: PM ruling pass C: gap above the upper side linings so they stay floating (= the 4 mm stack gap)"
equation "seam_gap_Ref = 2.26 mm" comment "DECIDED: PM ruling 2026-10-31 (Mechanical Checker F-001, F-005): the Joints Engineer's 2.26 mm at all nine site seam types, set by a metal stop (1.5 stop washer + 0.76 rivnut head; joints register section 2.8)"
equation "wall_z0_Ref = glide_h_Ref + band_h_Ref" comment "CALCULATION: base band top: glides + band"
equation "panel_z0_Ref = wall_z0_Ref + seam_gap_Ref" comment "CALCULATION: walls stand one seam_gap above the band top (joints register 2.8, IF-01)"
equation "wall_h_Ref = pod_h_Ref - wall_z0_Ref" comment "CALCULATION: 2290 = layout study v2_model wall_h"
equation "side_h_Ref = ( wall_h_Ref - 2 * seam_gap_Ref ) / 2" comment "CALCULATION: D-23: 2 sheets per side wall; the gap on the band and the horizontal seam (joints register 2.8)"
equation "back_oh_Ref = pod_h_Ref - outer_t_Ref - seam_gap_Ref - panel_z0_Ref" comment "CALCULATION: PM ruling 2026-10-31 (pass D, F-004): the back outer frames run up to the ceiling frame (pod_h - outer_t), less the seam_gap under it, closing the slot at the back top edge"
equation "back_ph_Ref = ( back_oh_Ref - seam_gap_Ref ) / 2" comment "CALCULATION: D-23: 4 sheets on the back, two equal rows with one seam_gap between them (joints register 2.8); the lower back linings match the lower row, as on the side walls"
equation "n_base_bolt_Ref = 4" comment "DECIDED: PM ruling 2026-10-31, J-BASE-01: bolts per panel along the band, evenly spaced"
equation "skin_t_Ref = 3 mm" comment "DECIDED: ACP skin, walls and ceiling (D-16; PM ruling 2026-10-31 on outer_t)"
equation "bond_t_Ref = 3 mm" comment "DECIDED: bond line between the ACP and the frame (PM ruling 2026-10-31 on outer_t)"
equation "frame_t_Ref = 40 mm" comment "DECIDED: aluminium frame tube depth, walls and ceiling (PM ruling 2026-10-31 on outer_t)"
equation "bolt_edge_inset_Ref = 220 mm" comment "DECIDED: PM ruling 2026-10-31: on every bolted edge the end bolts sit this far in from each panel end (the FRAME end, where the bolts go), the rest evenly spaced"
equation "spigot_inset_Ref = 100 mm" comment "DECIDED: PM ruling 2026-10-31: locating spigots this far in from each panel end (round hole at one end, slot at the other)"
equation "ceil_bolt_z_Ref = pod_h_Ref - outer_t_Ref + frame_t_Ref / 2" comment "DECIDED: PM ruling 2026-10-31, J-CEIL-01 wall to ceiling: the bolt line on the ceiling frame's centre (Z 2374)"
equation "pod_w = pod_w_Ref" comment "LINKED: pod_w_Ref, derived from 100000_P04_POD-SKELETON_CAD v4 (skeleton is the single source)"
equation "pod_d = pod_d_Ref" comment "LINKED: pod_d_Ref, derived from 100000_P04_POD-SKELETON_CAD v4 (skeleton is the single source)"
equation "pod_h = pod_h_Ref" comment "LINKED: pod_h_Ref, derived from 100000_P04_POD-SKELETON_CAD v4 (skeleton is the single source)"
equation "wall_depth = wall_depth_Ref" comment "LINKED: wall_depth_Ref, derived from 100000_P04_POD-SKELETON_CAD v4 (skeleton is the single source)"
equation "wall_z0 = wall_z0_Ref" comment "LINKED: wall_z0_Ref, derived from 100000_P04_POD-SKELETON_CAD v4 (skeleton is the single source)"
equation "panel_z0 = panel_z0_Ref" comment "LINKED: panel_z0_Ref, derived from 100000_P04_POD-SKELETON_CAD v4 (skeleton is the single source)"
equation "side_h = side_h_Ref" comment "LINKED: side_h_Ref, derived from 100000_P04_POD-SKELETON_CAD v4 (skeleton is the single source)"
equation "back_ph = back_ph_Ref" comment "LINKED: back_ph_Ref, derived from 100000_P04_POD-SKELETON_CAD v4 (skeleton is the single source)"
equation "stack_t = stack_t_Ref" comment "LINKED: stack_t_Ref, derived from 100000_P04_POD-SKELETON_CAD v4 (skeleton is the single source)"
equation "outer_t = outer_t_Ref" comment "LINKED: outer_t_Ref, derived from 100000_P04_POD-SKELETON_CAD v4 (skeleton is the single source)"
equation "cass_t = cass_t_Ref" comment "LINKED: cass_t_Ref, derived from 100000_P04_POD-SKELETON_CAD v4 (skeleton is the single source)"
equation "lin_gap = lin_gap_Ref" comment "LINKED: lin_gap_Ref, derived from 100000_P04_POD-SKELETON_CAD v4 (skeleton is the single source)"
equation "seam_gap = seam_gap_Ref" comment "LINKED: seam_gap_Ref, derived from 100000_P04_POD-SKELETON_CAD v4 (skeleton is the single source)"
equation "skin_t = skin_t_Ref" comment "LINKED: skin_t_Ref, derived from 100000_P04_POD-SKELETON_CAD v4 (skeleton is the single source)"
equation "bond_t = bond_t_Ref" comment "LINKED: bond_t_Ref, derived from 100000_P04_POD-SKELETON_CAD v4 (skeleton is the single source)"
equation "bolt_edge_inset = bolt_edge_inset_Ref" comment "LINKED: bolt_edge_inset_Ref, derived from 100000_P04_POD-SKELETON_CAD v4 (skeleton is the single source)"
equation "spigot_inset = spigot_inset_Ref" comment "LINKED: spigot_inset_Ref, derived from 100000_P04_POD-SKELETON_CAD v4 (skeleton is the single source)"
equation "n_base_bolt = n_base_bolt_Ref" comment "LINKED: n_base_bolt_Ref, derived from 100000_P04_POD-SKELETON_CAD v4 (skeleton is the single source)"
equation "ceil_bolt_z = ceil_bolt_z_Ref" comment "LINKED: ceil_bolt_z_Ref, derived from 100000_P04_POD-SKELETON_CAD v4 (skeleton is the single source)"
equation "tube_w = 20 mm" comment "CONFIRMED: D-34, D-54: aluminium tube 20 x 40 x 1.2; the 20 mm face carries the skin, so the 40 mm runs through the wall (outer_t = ACP 3 + frame 40). The joint register may turn it for the bond width (HOLD)"
equation "tube_d = outer_t - skin_t - bond_t" comment "CALCULATION: frame depth = outer panel 46 - skin 3 - bond 3 = 40 (D-34)"
equation "tube_t = 1.2 mm" comment "CONFIRMED: D-34, D-54, D-85: perimeter members (rails, front and back stiles) keep the 1.2 mm wall; they carry the rivnuts (grip check passed)"
equation "stud_t = 1.0 mm" comment "CONFIRMED: D-85 (weight): intermediate studs at a 1.0 mm wall; they carry no rivnut, only the skin's bond line"
equation "stile_pitch_max = 400 mm" comment "CONFIRMED: D-16, D-34: members 400 mm apart or less, to keep the ACP flat"
equation "pnl_len = wall_depth - seam_gap" comment "CALCULATION: D-49 depth 1495 less the 2.26 gap at the decor back plate (PM ruling on F-008): 1492.74"
equation "pnl_h = pod_h - ( panel_z0 + side_h + seam_gap )" comment "CALCULATION: lower: skeleton side_h (2 sheets per side wall, D-23); upper: from one seam gap above the lower row to the roof datum pod_h, as the skeleton's envelope (equal to side_h at P04 values)"
equation "skin_ret = outer_t - skin_t" comment "ASSUMPTION: back return of the side skin: covers the frame's back end at the corner, where the side skin covers the back panel's edge (D-55; sample drawing D04). V-groove and fold per the ACP maker (HOLD H16)"
equation "skin_setback = 0 mm" comment "ASSUMPTION: skin edge set back from the frame's top and bottom edges: 0, so the outside reveal equals the 2.26 seam gap (D-23: crisp, aligned reveals; joints register 2.8 leaves the setback to the WALL drawing)"
equation "frm_len = pnl_len - skin_t" comment "CALCULATION: the frame stops at the inside of the skin's back return"
equation "frm_h = pnl_h" comment "ASSUMPTION: the frame fills the skeleton envelope height; seam and base gasket gaps are set by the joint register (HOLD)"
equation "corner_w = 40 mm" comment "CONFIRMED: the side panel's back member is 40 x 40 x 1.2 (PM ruling on the joints register, item 3, 2026-10-31; register F2, FR-06): the back corner joint needs a 37+ mm overlap for the rivnut and the bolt"
equation "stile_n_mid = ceil(( frm_len - tube_w / 2 - corner_w / 2 ) / stile_pitch_max) - 1" comment "CALCULATION: intermediate stiles so that no stile pitch (centre to centre) exceeds stile_pitch_max"
equation "stile_pitch = ( frm_len - tube_w / 2 - corner_w / 2 ) / ( stile_n_mid + 1 )" comment "CALCULATION: equal stile pitch, centre to centre, from the front stile to the 40 mm back stile"
equation "top_h = corner_w" comment "CONFIRMED: top member height: 20 on a lower panel; 40 x 40 on an upper panel, where the ceiling bolts in (PM ruling R-J3, joints register FR-06)"
equation "stile_len = frm_h - tube_w - top_h" comment "CALCULATION: stiles fit between the full-length rails (butt joints)"
equation "ceil_bolt_dz = pod_h - ceil_bolt_z" comment "CALCULATION: J-CEIL-01 side bolts on the ceiling frame tube's centre: the skeleton's ceil_bolt_z, Z 2374 on P04 (joints register R-J15, FR-07)"
equation "fill_t = tube_d" comment "CALCULATION: 40 mm PET fill fills the frame depth (D-34; layout study 40 mm)"
equation "bolt_d = 7 mm" comment "CONFIRMED: PM ruling on F-009: bolt holes 7.0 (0.51 float), position tolerance 0.4 (+-0.2) from the spigot hole, CNC or drill jig (joints register FR-02)"
equation "access_d = 19 mm" comment "CALCULATION: register FR-03: passes the 18 mm head washer (ISO 7093-1, R-J10), the M6 head and the 5 mm key; holds the grommet retainer (H-02)"